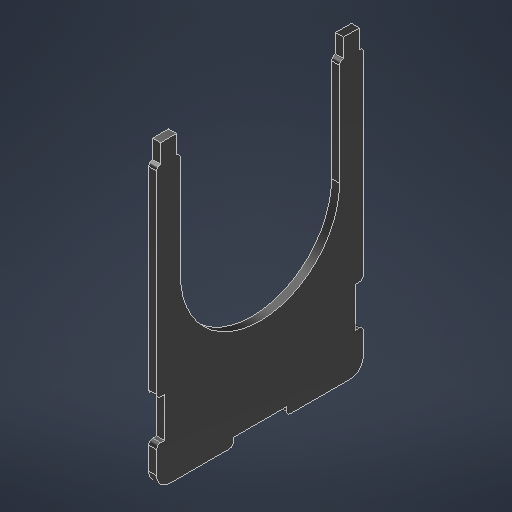
# Autodesk Inventor part: SlotBack
Saved by Autodesk Inventor 2027.1 (Build 311270010, 270A)
## iProperties
Created: 2026-10-20
Part Number: SlotBack
Material: MDF Medium Density Fiberboard
Document SubType Name: Modeling
Designer: SDS Scholar
Density: 0.8 g/cm^3
Appearance: Glossy - Black
Mass: 10.2929 g
Surface Area: 100.46 cm^2
Volume: 12.8662 cm^3
Author: SDS Scholar
Autodesk Inventor part; units mm, degrees
ref_plane "YZ Plane" through (0, 0, 0) normal (1, 0, 0) x (0, 1, 0)
ref_plane "XZ Plane" through (0, 0, 0) normal (0, 1, 0) x (-1, 0, 0)
ref_plane "XY Plane" through (0, 0, 0) normal (0, 0, 1) x (1, 0, 0)
sketch "Sketch1" plane through (0, 0, 0) normal (1, 0, 0) x (0, 1, 0)
  line L0 (53, 36) -> (-53, 36)
  line L1 (-53, 36) -> (-53, -36)
  line L2 (-53, -36) -> (53, -36)
  line L3 (53, -36) -> (53, 36)
  line L4 (-53, 36) -> (53, 36)
  line L5 (53, 36) -> (53, 39)
  line L6 (53, 39) -> (-53, 39)
  line L7 (-53, 39) -> (-53, 36)
  line L8 (-53, -10) -> (-50, -10)
  line L9 (-50, -10) -> (-50, 10)
  line L10 (-50, 10) -> (-53, 10)
  line L11 (-53, 10) -> (-53, -10)
  line L12 (-8, 36) -> (-8, -36) construction
  line L13 (-53, 0) -> (-8, 0) construction
  line L14 (-38, 36) -> (-23, 36)
  line L15 (-23, 36) -> (-23, 39)
  line L16 (-23, 39) -> (-38, 39)
  line L17 (-38, 39) -> (-38, 36)
  line L18 (-8, 0) -> (53, 0) construction
  line L19 (53, -36) -> (53, -39)
  line L20 (53, -39) -> (-53, -39)
  line L21 (-53, -39) -> (-53, -36)
  line L22 (-23, -36) -> (-23, -39)
  line L23 (-23, -39) -> (-38, -39)
  line L24 (-38, -39) -> (-38, -36)
  line L25 (13, 36) -> (13, -36) construction
  line L26 (53, -30) -> (13, -30)
  line L27 (13, -30) -> (13, 30)
  line L28 (13, 30) -> (53, 30)
  line L29 (53, 30) -> (53, -30)
  arc A0 (13, 30) -> (13, -30) centre (13, 0) ccw
  point P0 (0, 0)
  point P1 (0, -36)
  point P2 (0, 0)
  point P3 (-50, 0)
  point P4 (-53, 10)
  point P5 (-30.5, 39)
  point P6 (-30.5, 0)
  point P7 (53, -36)
  point P8 (-23, -36)
  point P9 (-38, -39)
  point P10 (-38, -36)
  point P11 (-23, 36)
  point P12 (-38, 36)
  point P13 (-38, 39)
  point P14 (53, 0)
  point P15 (53, 30)
  dimension "d0" = 72
  dimension "d1" = 106
  dimension "d8" = 3
  dimension "d10" = 20
  dimension "d11" = 3
  dimension "d12" = 45
  dimension "d13" = 45
  dimension "d14" = 15
  dimension "d15" = 40
  dimension "d16" = 60
  dimension "d17" = 30
  constraints: 60 end point, 10 parallel, 10 point on line, 9 midpoint, 7 perpendicular, 7 symmetric about line, 5 horizontal, 2 coincident, 2 horizontal alignment, 2 point on circle, 2 vertical alignment, 1 centre point
  measures "d0" distance of L0.end L1.end
  measures "d1" distance of L1.end L2.end
  measures "d8" distance of L4.end L5.end
  measures "d10" distance of L8.end L9.end
  measures "d11" distance of L9.end L10.end
  measures "d12" distance of L13.start L13.end
  measures "d13" distance between parallel lines of L1 L12
  measures "d14" distance of L15.end L16.end
  measures "d15" distance between parallel lines of L3 L25
  measures "d16" distance between parallel lines of L26 L28
  measures "d17" radius of A0
extrude "Extrusion1" add sketch "Sketch1" along normal blind 3 contours L3 L28 A0 L26 L2 L1 L8 L9 L10 L0 | L0 L15 L6 L5 | L0 L7 L6 L17 | L19 L20 L22 L2 | L24 L20 L21 L2
fillet "Fillet1" radius 1.5 10 edges at (1.5, -53, 10) (1.5, -53, -10) (1.5, -38, 39) (1.5, -23, 39) (1.5, -38, -39) (1.5, -23, -39) (1.5, 53, 39) (1.5, 53, 30) (1.5, 53, -39) (1.5, 53, -30)
fillet "Fillet3" radius 5 2 edges at (1.5, -53, -39) (1.5, -53, 39)
sketch "Sketch2" plane through (0, 0, 0) normal (-1, 0, 0) x (0, 0, 1)
  line L0 (10, -50) -> (-10, -50) projected
  line L1 (0, -50) -> (0, -17) construction
  arc A0 (-30, 13) -> (30, 13) centre (0, 13) ccw projected
  arc A1 (31.5, 53) -> (30, 51.5) centre (31.5, 51.5) ccw projected
  line L2 (31.5, 53) -> (37.5, 53)
  line L3 (37.5, 53) -> (37.5, 60)
  line L4 (37.5, 60) -> (31.5, 60)
  line L5 (31.5, 60) -> (31.5, 53)
  arc A2 (-30, 51.5) -> (-31.5, 53) centre (-31.5, 51.5) ccw
  line L6 (-31.5, 53) -> (-37.5, 53)
  line L7 (-37.5, 53) -> (-37.5, 60)
  line L8 (-37.5, 60) -> (-31.5, 60)
  line L9 (-31.5, 60) -> (-31.5, 53)
  point P0 (0, 0)
  dimension "d19" = 6
  dimension "d20" = 7
  constraints: 18 end point, 6 symmetric about line, 5 point on circle, 2 parallel, 1 centre point, 1 horizontal, 1 midpoint, 1 perpendicular, 1 other
  measures "d19" distance of L4.end L3.end
  measures "d20" distance of L3.end L2.end
extrude "Extrusion2" add sketch "Sketch2" against normal blind 3
equation "\"d12\" = ProductTotalHeight"
equation "\"d13\" = ProductTotalHeight"
equation "\"d17\" = 0.5 * d16"
equation "\"GridProcutClearance\" = 5"
equation "\"GridBorderThickness\" = 5"
equation "\"GridBorderFillets\" = 7"
equation "\"GridTotalSize\" = 65"
equation "\"GridRobotClearance\" = 65"
equation "\"AluminiumExtrusionClearance\" = 35"
equation "\"BaseTotalLength\" = 885"
equation "\"WorkspaceLength\" = 515"
equation "\"WorkspaceHeight\" = 183"
equation "\"AxesBaseFillet\" = 15"
equation "\"Zaxis\" = 197"
equation "\"ProductTotalHeight\" = 45"
equation "\"VerticalStroke\" = 105"
equation "\"BackArea\" = 165"
equation "\"CylinderStroke\" = 75"
equation "\"BoxesWidth\" = 125"
equation "\"BaseWoodThickness\" = 7"
equation "\"Kerf\" = 0.3"
equation "\"RxThickness\" = 1.8"
equation "\"support_2\" = 265"
body "Solid1"
